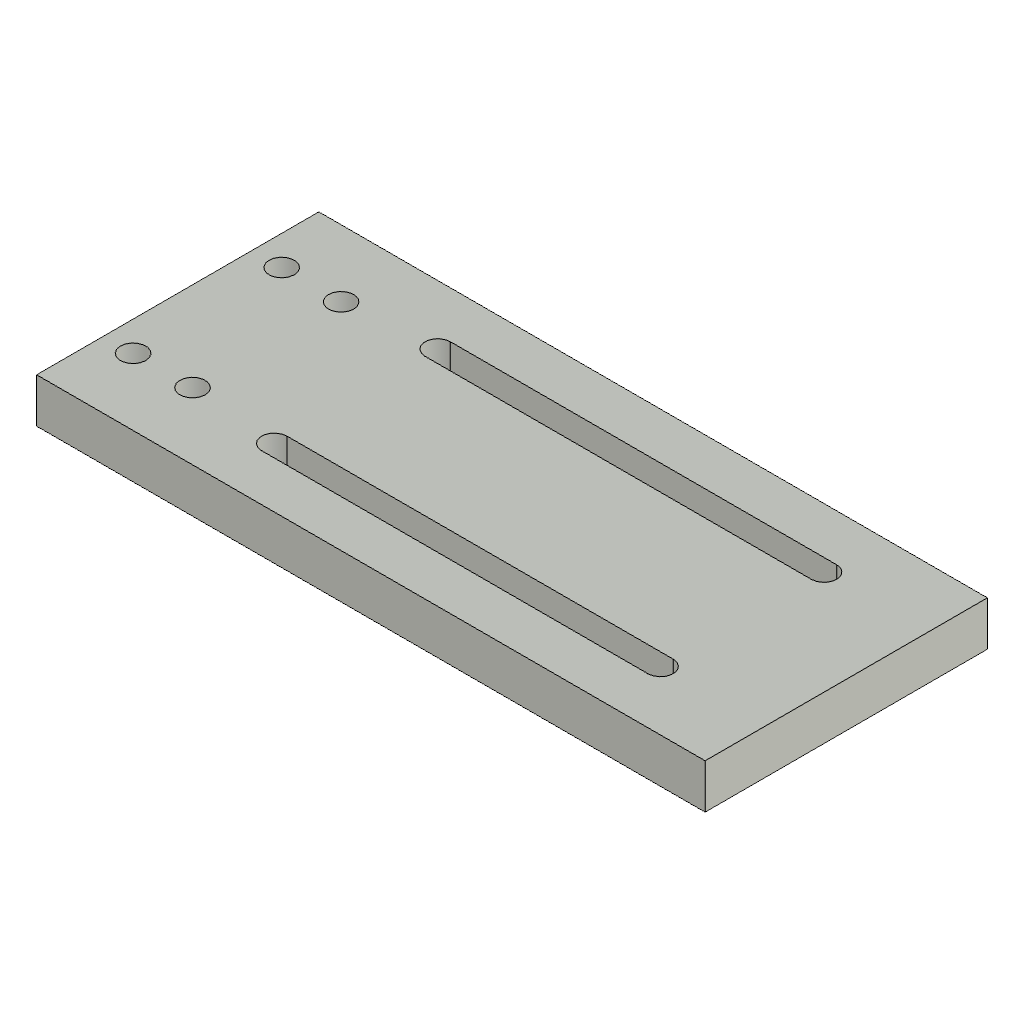
tip_adapter (Autodesk Fusion 360 design; units mm, degrees)
part number: 2026-10-10-16-37-39-346
Autodesk Fusion 360 part; units mm, degrees
sketch "Adapter plate sketch" plane through (0, 0, 0) normal (0, 0, 1) x (1, 0, 0)
  line L0 (0, -19) -> (90, -19)
  line L1 (90, -19) -> (90, 19)
  line L2 (90, 19) -> (0, 19)
  line L3 (0, 19) -> (0, -19)
extrude "Adapter plate" add sketch "Adapter plate sketch" along normal blind 6
ref_plane "WorkPlane1" through (0, 0, -0.05) normal (0, 0, 1) x (1, 0, 0)
sketch "Wing adapter bolt 4 -10 sketch" plane through (0, 0, -0.05) normal (0, 0, 1) x (1, 0, 0)
  circle A0 centre (4, -10) radius 1.7
  dimension "d241" = 3.4
  measures "d241" diameter of A0
extrude "Wing adapter bolt 4 -10" cut sketch "Wing adapter bolt 4 -10 sketch" along normal blind 6.1
ref_plane "WorkPlane2" through (0, 0, -0.05) normal (0, 0, 1) x (1, 0, 0)
sketch "Wing adapter bolt 4 10 sketch" plane through (0, 0, -0.05) normal (0, 0, 1) x (1, 0, 0)
  circle A0 centre (4, 10) radius 1.7
  dimension "d246" = 3.4
  measures "d246" diameter of A0
extrude "Wing adapter bolt 4 10" cut sketch "Wing adapter bolt 4 10 sketch" along normal blind 6.1
ref_plane "WorkPlane3" through (0, 0, -0.05) normal (0, 0, 1) x (1, 0, 0)
sketch "Wing adapter bolt 12 -10 sketch" plane through (0, 0, -0.05) normal (0, 0, 1) x (1, 0, 0)
  circle A0 centre (12, -10) radius 1.7
  dimension "d251" = 3.4
  measures "d251" diameter of A0
extrude "Wing adapter bolt 12 -10" cut sketch "Wing adapter bolt 12 -10 sketch" along normal blind 6.1
ref_plane "WorkPlane4" through (0, 0, -0.05) normal (0, 0, 1) x (1, 0, 0)
sketch "Wing adapter bolt 12 10 sketch" plane through (0, 0, -0.05) normal (0, 0, 1) x (1, 0, 0)
  circle A0 centre (12, 10) radius 1.7
  dimension "d256" = 3.4
  measures "d256" diameter of A0
extrude "Wing adapter bolt 12 10" cut sketch "Wing adapter bolt 12 10 sketch" along normal blind 6.1
ref_plane "WorkPlane5" through (0, 0, -0.05) normal (0, 0, 1) x (1, 0, 0)
sketch "Fixed mount sliding rail -11 sketch" plane through (0, 0, -0.05) normal (0, 0, 1) x (1, 0, 0)
  arc A0 (24, -9.3) -> (24, -12.7) centre (24, -11) ccw
  line L0 (24, -9.3) -> (76, -9.3)
  arc A1 (76, -12.7) -> (76, -9.3) centre (76, -11) ccw
  line L1 (76, -12.7) -> (24, -12.7)
extrude "Fixed mount sliding rail -11" cut sketch "Fixed mount sliding rail -11 sketch" along normal blind 6.1
ref_plane "WorkPlane6" through (0, 0, -0.05) normal (0, 0, 1) x (1, 0, 0)
sketch "Fixed mount sliding rail 11 sketch" plane through (0, 0, -0.05) normal (0, 0, 1) x (1, 0, 0)
  arc A0 (24, 12.7) -> (24, 9.3) centre (24, 11) ccw
  line L0 (24, 12.7) -> (76, 12.7)
  arc A1 (76, 9.3) -> (76, 12.7) centre (76, 11) ccw
  line L1 (76, 9.3) -> (24, 9.3)
extrude "Fixed mount sliding rail 11" cut sketch "Fixed mount sliding rail 11 sketch" along normal blind 6.1
equation "d241 = m3Clearance"
equation "d246 = m3Clearance"
equation "d251 = m3Clearance"
equation "d256 = m3Clearance"
equation "m3Clearance = 3.4 mm" comment "Root registration and tip adapter holes"
named bodies: "tip_adapter - printable solid"
